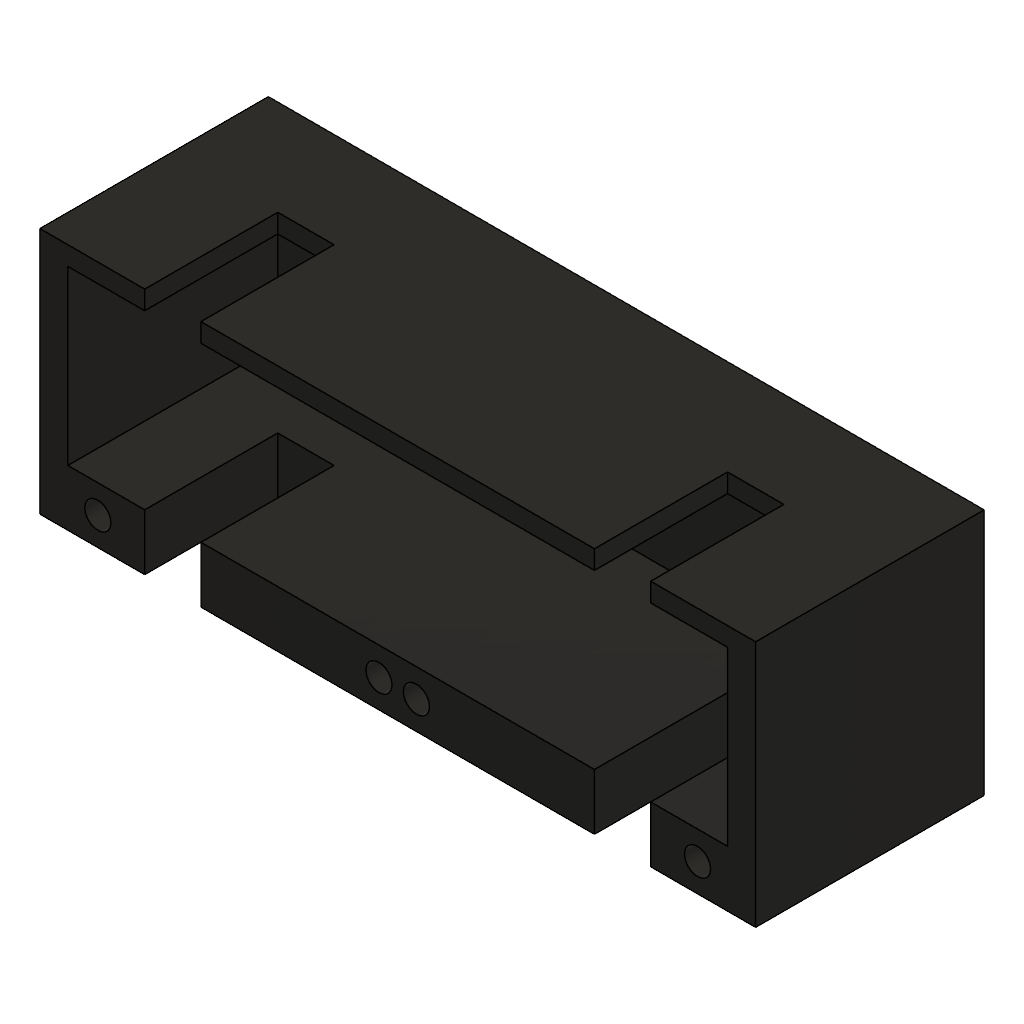
Robot_Assembly (Autodesk Fusion 360 archive; units mm, degrees)
design "Motor cradles"
part number: 2026-11-12-22-37-27-896
Autodesk Fusion 360 part; units mm, degrees
sketch "Sketch3" plane through (0, 0, 0) normal (0, 0, 1) x (1, 0, 0)
  line L0 (38.2, -13.2) -> (-38.2, -13.2)
  line L1 (-38.2, -13.2) -> (-38.2, 13.2)
  line L2 (-38.2, 13.2) -> (38.2, 13.2)
  line L3 (38.2, 13.2) -> (38.2, -13.2)
  line L4 (38.2, -13.2) -> (-38.2, 13.2) construction
  line L5 (-38.2, -13.2) -> (38.2, 13.2) construction
  dimension "d11" = 76.4
  dimension "d12" = 26.4
  constraint horizontal L0
  constraint perpendicular L0 L1
  constraint parallel L0 L2
  constraint parallel L1 L3
  constraint coincident L4 origin
  constraint coincident L5 origin
  measures "d11" distance of L0.start L0.end
  measures "d12" distance of L0.start L2.end
extrude "Extrude2" add sketch "Sketch3" along normal blind 24.4
sketch "Sketch5" plane through (0, 0, 24.4) normal (0, 0, 1) x (1, 0, 0)
  line L0 (38.2, 13.2) -> (-38.2, 13.2)
  line L1 (-38.2, 13.2) -> (-38.2, -13.2)
  line L2 (-38.2, -13.2) -> (38.2, -13.2)
  line L3 (38.2, -13.2) -> (38.2, 13.2)
  line L4 (35.2, -7.2) -> (-35.2, -7.2)
  line L5 (-35.2, -7.2) -> (-35.2, 11.2)
  line L6 (-35.2, 11.2) -> (35.2, 11.2)
  line L7 (35.2, 11.2) -> (35.2, -7.2)
  line L8 (35.2, -7.2) -> (-35.2, 11.2) construction
  line L9 (-35.2, -7.2) -> (35.2, 11.2) construction
  circle A0 centre (-32, -10.2) radius 1.4
  circle A1 centre (-2, -10.2) radius 1.4
  circle A2 centre (2, -10.2) radius 1.4
  circle A3 centre (32, -10.2) radius 1.4
  point P0 (0, 2)
  dimension "d15" = 6
  dimension "d16" = 3
  dimension "d17" = 70.4
  dimension "d18" = 18.4
  dimension "d19" = 2.8
  dimension "d20" = 3
  dimension "d21" = 6.2
  dimension "d22" = 2.8
  dimension "d23" = 3
  dimension "d24" = 36.2
  dimension "d25" = 2.8
  dimension "d26" = 3
  dimension "d27" = 40.2
  dimension "d28" = 2.8
  dimension "d29" = 3
  dimension "d30" = 70.2
  constraint horizontal L4
  constraint perpendicular L4 L5
  constraint parallel L4 L6
  constraint parallel L5 L7
  constraint coincident L8 P0
  constraint coincident L9 P0
  measures "d15" distance of L2 L4
  measures "d16" distance of L1 L5
  measures "d17" distance of L4.start L4.end
  measures "d18" distance of L4.start L6.end
  measures "d19" diameter of A0
  measures "d20" distance of L2 A0.centre
  measures "d21" distance of L1 A0.centre
  measures "d22" diameter of A1
  measures "d23" distance of L2 A1.centre
  measures "d24" distance of L1 A1.centre
  measures "d25" diameter of A2
  measures "d26" distance of L2 A2.centre
  measures "d27" distance of L1 A2.centre
  measures "d28" diameter of A3
  measures "d29" distance of L2 A3.centre
  measures "d30" distance of L1 A3.centre
extrude "Extrude3" cut sketch "Sketch5" against normal blind 22.4 contours L4 L5 L6 L7
extrude "Extrude4" cut sketch "Sketch5" against normal blind 10 contours A0 | A1 | A2 | A3
sketch "Sketch6" plane through (0, 0, 24.4) normal (0, 0, 1) x (1, 0, 0)
  line L0 (38.2, 13.2) -> (-38.2, 13.2)
  line L1 (-38.2, 13.2) -> (-38.2, -13.2)
  line L2 (-38.2, -13.2) -> (38.2, -13.2)
  line L3 (38.2, -13.2) -> (38.2, 13.2)
  line L4 (-35.2, -7.2) -> (-35.2, 11.2)
  line L5 (-35.2, 11.2) -> (35.2, 11.2)
  line L6 (35.2, 11.2) -> (35.2, -7.2)
  line L7 (35.2, -7.2) -> (-35.2, -7.2)
  circle A0 centre (32, -10.2) radius 1.4
  circle A1 centre (-32, -10.2) radius 1.4
  circle A2 centre (2, -10.2) radius 1.4
  circle A3 centre (-2, -10.2) radius 1.4
  line L8 (-27, 17.0474) -> (-21, 17.0474)
  line L9 (-21, 17.0474) -> (-21, -21.5101)
  line L10 (-21, -21.5101) -> (-27, -21.5101)
  line L11 (-27, -21.5101) -> (-27, 17.0474)
  line L12 (21, 17.0474) -> (27, 17.0474)
  line L13 (27, 17.0474) -> (27, -21.5101)
  line L14 (27, -21.5101) -> (21, -21.5101)
  line L15 (21, -21.5101) -> (21, 17.0474)
  dimension "d35" = 6
  dimension "d36" = 11.2
  dimension "d37" = 6
  dimension "d38" = 59.2
  constraint horizontal L8
  constraint vertical L9
  constraint horizontal L10
  constraint vertical L11
  constraint horizontal L12
  constraint vertical L13
  constraint horizontal L14
  constraint vertical L15
  measures "d35" distance of L8.start L8.end
  measures "d36" distance of L1 L11
  measures "d37" distance of L12.start L12.end
  measures "d38" distance of L1 L15
extrude "Extrude5" cut sketch "Sketch6" against normal blind 14.2 contours L0 L5 L13 L15 | L0 L12 L13 L15 | L5 L7 L13 L15 | L2 L13 L14 L15 | L2 L7 L13 L15 | L0 L5 L9 L11 | L0 L8 L9 L11 | L5 L7 L9 L11 | L2 L9 L10 L11 | L2 L7 L9 L11

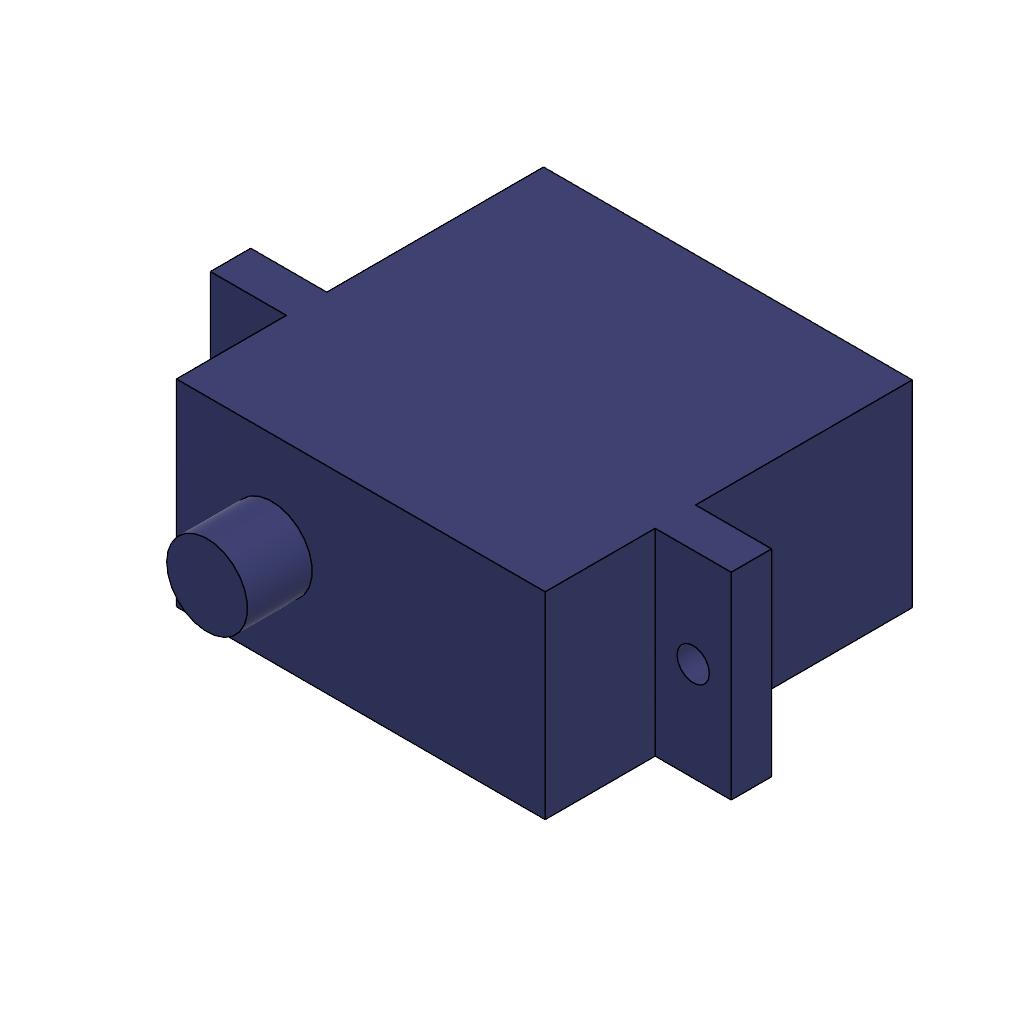
design "Servo_SG90"
part number: 2026-11-06-21-26-01-981
Autodesk Fusion 360 part; units mm, degrees
sketch "Sketch1" plane through (0, 0, 0) normal (0, 0, 1) x (1, 0, 0)
  line L0 (11.4, -6.1) -> (-11.4, -6.1)
  line L1 (-11.4, -6.1) -> (-11.4, 6.1)
  line L2 (-11.4, 6.1) -> (11.4, 6.1)
  line L3 (11.4, 6.1) -> (11.4, -6.1)
  line L4 (11.4, -6.1) -> (-11.4, 6.1) construction
  line L5 (-11.4, -6.1) -> (11.4, 6.1) construction
  dimension "d1" = 22.8
  dimension "d2" = 12.2
  constraint horizontal L0
  constraint perpendicular L0 L1
  constraint parallel L0 L2
  constraint parallel L1 L3
  constraint coincident L4 origin
  constraint coincident L5 origin
  measures "d1" distance of L1.end L2.end
  measures "d2" distance of L0.start L2.end
sketch "Sketch2" plane through (0, 0, 0) normal (0, 0, 1) x (1, 0, 0)
  line L0 (11.4, -6.1) -> (-11.4, -6.1)
  line L1 (-11.4, -6.1) -> (-11.4, 6.1)
  line L2 (-11.4, 6.1) -> (11.4, 6.1)
  line L3 (11.4, 6.1) -> (11.4, -6.1)
  line L4 (11.4, -6.1) -> (-11.4, 6.1) construction
  line L5 (-11.4, -6.1) -> (11.4, 6.1) construction
  dimension "d5" = 22.8
  dimension "d6" = 12.2
  constraint horizontal L0
  constraint perpendicular L0 L1
  constraint parallel L0 L2
  constraint parallel L1 L3
  constraint coincident L4 origin
  constraint coincident L5 origin
  measures "d5" distance of L0.start L0.end
  measures "d6" distance of L0.start L2.end
extrude "Extrude2" add sketch "Sketch2" along normal blind 22.7
sketch "Sketch3" plane through (0, 0, 22.7) normal (0, 0, 1) x (1, 0, 0)
  line L0 (11.4, 6.1) -> (-11.4, 6.1)
  line L1 (-11.4, 6.1) -> (-11.4, -6.1)
  line L2 (-11.4, -6.1) -> (11.4, -6.1)
  line L3 (11.4, -6.1) -> (11.4, 6.1)
  line L4 (16.1, -6.1) -> (-16.1, -6.1)
  line L5 (-16.1, -6.1) -> (-16.1, 6.1)
  line L6 (-16.1, 6.1) -> (16.1, 6.1)
  line L7 (16.1, 6.1) -> (16.1, -6.1)
  line L8 (16.1, -6.1) -> (-16.1, 6.1) construction
  line L9 (-16.1, -6.1) -> (16.1, 6.1) construction
  dimension "d9" = 12.2
  dimension "d10" = 32.2
  constraint horizontal L4
  constraint perpendicular L4 L5
  constraint parallel L4 L6
  constraint parallel L5 L7
  constraint coincident L8 origin
  constraint coincident L9 origin
  measures "d9" distance of L4.end L5.end
  measures "d10" distance of L5.end L6.end
sketch "Sketch4" plane through (0, 0, 38.6) normal (0, 0, 1) x (1, 0, 0)
ref_plane "WorkPlane1" through (0, 0, 13.4) normal (0, 0, 1) x (1, 0, 0)
sketch "Sketch6" plane through (0, 0, 13.4) normal (0, 0, 1) x (1, 0, 0)
  line L0 (16.1, -6.1) -> (-16.1, -6.1)
  line L1 (-16.1, -6.1) -> (-16.1, 6.1)
  line L2 (-16.1, 6.1) -> (16.1, 6.1)
  line L3 (16.1, 6.1) -> (16.1, -6.1)
  line L4 (16.1, -6.1) -> (-16.1, 6.1) construction
  line L5 (-16.1, -6.1) -> (16.1, 6.1) construction
  dimension "d18" = 32.2
  dimension "d19" = 12.2
  constraint horizontal L0
  constraint perpendicular L0 L1
  constraint parallel L0 L2
  constraint parallel L1 L3
  constraint coincident L4 origin
  constraint coincident L5 origin
  measures "d18" distance of L1.end L2.end
  measures "d19" distance of L0.start L2.end
extrude "Extrude4" add sketch "Sketch6" along normal blind 2.5
sketch "Sketch7" plane through (0, 0, 15.9) normal (0, 0, 1) x (1, 0, 0)
  line L0 (-11.4, -6.1) -> (-11.4, 6.1)
  line L1 (-11.4, 6.1) -> (-16.1, 6.1)
  line L2 (-16.1, 6.1) -> (-16.1, -6.1)
  line L3 (-16.1, -6.1) -> (-11.4, -6.1)
  circle A0 centre (-13.75, 0) radius 1
  dimension "d22" = 2
  dimension "d23" = 2.35
  dimension "d24" = 6.1
  measures "d22" diameter of A0
  measures "d23" distance of L2 A0.centre
  measures "d24" distance of L1 A0.centre
sketch "Sketch8" plane through (0, 0, 15.9) normal (0, 0, 1) x (1, 0, 0)
  line L0 (11.4, 6.1) -> (11.4, -6.1)
  line L1 (11.4, -6.1) -> (16.1, -6.1)
  line L2 (16.1, -6.1) -> (16.1, 6.1)
  line L3 (16.1, 6.1) -> (11.4, 6.1)
  circle A0 centre (13.75, 0) radius 1
  dimension "d25" = 2
  dimension "d26" = 2.35
  dimension "d27" = 6.1
  measures "d25" diameter of A0
  measures "d26" distance of L0 A0.centre
  measures "d27" distance of L3 A0.centre
extrude "Extrude5" cut sketch "Sketch7" sketch "Sketch8" against normal blind 10 contours A0 of sketch 2 contours A0
sketch "Sketch9" plane through (0, 0, 22.7) normal (0, 0, 1) x (1, 0, 0)
  line L0 (11.4, 6.1) -> (-11.4, 6.1)
  line L1 (-11.4, 6.1) -> (-11.4, -6.1)
  line L2 (-11.4, -6.1) -> (11.4, -6.1)
  line L3 (11.4, -6.1) -> (11.4, 6.1)
  circle A0 centre (-5.5, 0) radius 2.5
  dimension "d30" = 5
  dimension "d31" = 5.9
  dimension "d32" = 6.1
  measures "d30" diameter of A0
  measures "d31" distance of L1 A0.centre
  measures "d32" distance of L0 A0.centre
extrude "Extrude6" add sketch "Sketch9" along normal blind 4 contours A0

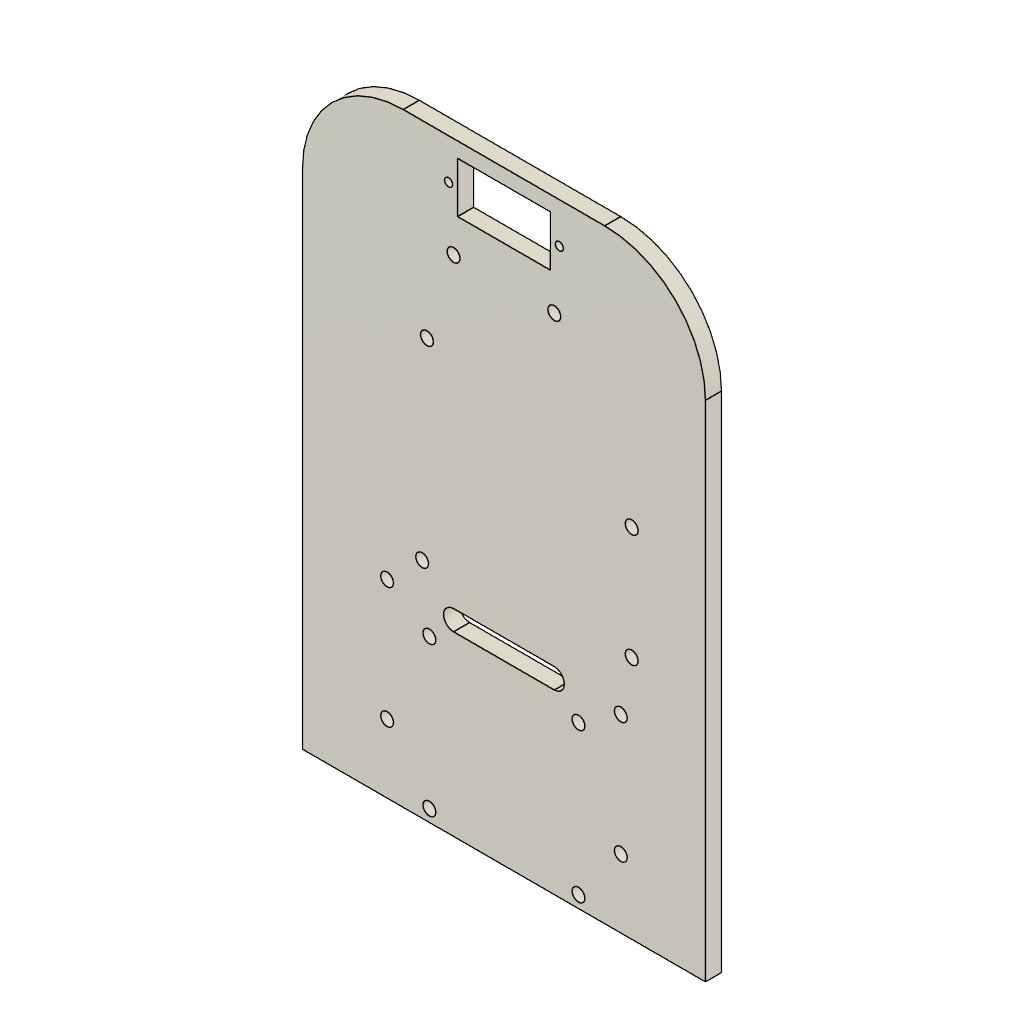
design "Chassis plate"
part number: 2026-11-10-16-59-27-639
Autodesk Fusion 360 part; units mm, degrees
sketch "Sketch1" plane through (0, 0, 0) normal (0, 0, 1) x (1, 0, 0)
  line L0 (50, -75) -> (-50, -75)
  line L1 (-50, -75) -> (-50, 50)
  line L2 (-25, 75) -> (25, 75)
  line L3 (50, 50) -> (50, -75)
  line L4 (50, -75) -> (-50, 75) construction
  line L5 (-50, -75) -> (50, 75) construction
  arc A0 (-25, 75) -> (-50, 50) centre (-25, 50) ccw
  arc A1 (50, 50) -> (25, 75) centre (25, 50) ccw
  circle A2 centre (-18.5, -72) radius 1.6
  circle A3 centre (18.5, -72) radius 1.6
  circle A4 centre (-18.5, -35) radius 1.6
  circle A5 centre (18.5, -35) radius 1.6
  circle A6 centre (-20.3, -19.5) radius 1.6
  circle A7 centre (-19.1, 28.8) radius 1.6
  circle A8 centre (31.7, -14.4) radius 1.6
  circle A9 centre (31.7, 13.6) radius 1.6
  circle A10 centre (-29, -58) radius 1.6
  circle A11 centre (-29, -28) radius 1.6
  circle A12 centre (29, -58) radius 1.6
  circle A13 centre (29, -28) radius 1.6
  circle A14 centre (-12.5, 50) radius 1.6
  circle A15 centre (12.5, 50) radius 1.6
  circle A16 centre (-13.75, 65) radius 1
  circle A17 centre (13.75, 65) radius 1
  line L6 (11.5, 58.75) -> (-11.5, 58.75)
  line L7 (-11.5, 58.75) -> (-11.5, 71.25)
  line L8 (-11.5, 71.25) -> (11.5, 71.25)
  line L9 (11.5, 71.25) -> (11.5, 58.75)
  line L10 (11.5, 58.75) -> (-11.5, 71.25) construction
  line L11 (-11.5, 58.75) -> (11.5, 71.25) construction
  line L12 (-12.5, -31) -> (12.5, -31)
  arc A18 (12.5, -31) -> (12.5, -26) centre (12.5, -28.5) ccw
  line L13 (12.5, -26) -> (-12.5, -26)
  arc A19 (-12.5, -26) -> (-12.5, -31) centre (-12.5, -28.5) ccw
  point P0 (0, 65)
  dimension "d1" = 100
  dimension "d2" = 150
  dimension "d3" = 25
  dimension "d4" = 25
  dimension "d5" = 3.2
  dimension "d6" = 31.5
  dimension "d7" = 3
  dimension "d8" = 3.2
  dimension "d9" = 3
  dimension "d10" = 68.5
  dimension "d11" = 3.2
  dimension "d12" = 31.5
  dimension "d13" = 40
  dimension "d14" = 3.2
  dimension "d15" = 68.5
  dimension "d16" = 40
  dimension "d17" = 3.2
  dimension "d18" = 29.7
  dimension "d19" = 55.5
  dimension "d20" = 3.2
  dimension "d21" = 30.9
  dimension "d22" = 103.8
  dimension "d23" = 3.2
  dimension "d24" = 81.7
  dimension "d25" = 60.6
  dimension "d26" = 3.2
  dimension "d27" = 81.7
  dimension "d28" = 88.6
  dimension "d29" = 3.2
  dimension "d30" = 21
  dimension "d31" = 17
  dimension "d32" = 3.2
  dimension "d33" = 21
  dimension "d34" = 47
  dimension "d35" = 3.2
  dimension "d36" = 79
  dimension "d37" = 17
  dimension "d38" = 3.2
  dimension "d39" = 79
  dimension "d40" = 47
  dimension "d41" = 3.2
  dimension "d42" = 37.5
  dimension "d43" = 125
  dimension "d44" = 3.2
  dimension "d45" = 62.5
  dimension "d46" = 125
  dimension "d47" = 2
  dimension "d48" = 36.25
  dimension "d49" = 140
  dimension "d50" = 2
  dimension "d51" = 63.75
  dimension "d52" = 140
  dimension "d53" = 12.5
  dimension "d54" = 23
  dimension "d55" = 50
  dimension "d56" = 140
  dimension "d57" = 5
  dimension "d58" = 37.5
  dimension "d59" = 46.5
  constraint horizontal L0
  constraint perpendicular L0 L1
  constraint parallel L0 L2
  constraint parallel L1 L3
  constraint coincident L4 origin
  constraint coincident L5 origin
  constraint coincident L4.end L2
  constraint coincident L4.end L1
  constraint tangent L2 A0
  constraint tangent L1 A0
  constraint coincident L5.end L2
  constraint coincident L5.end L3
  constraint tangent L2 A1
  constraint tangent L3 A1
  constraint horizontal L6
  constraint perpendicular L6 L7
  constraint parallel L6 L8
  constraint parallel L7 L9
  constraint coincident L10 P0
  constraint coincident L11 P0
  constraint tangent L12 A18
  constraint tangent A18 L13
  constraint parallel L12 L13
  constraint tangent L13 A19
  constraint tangent L12 A19
  measures "d1" distance of L0.start L0.end
  measures "d2" distance of L0.start L5.end
  measures "d3" radius of A0
  measures "d4" radius of A1
  measures "d5" diameter of A2
  measures "d6" distance of L1 A2.centre
  measures "d7" distance of L0 A2.centre
  measures "d8" diameter of A3
  measures "d9" distance of L0 A3.centre
  measures "d10" distance of L1 A3.centre
  measures "d11" diameter of A4
  measures "d12" distance of L1 A4.centre
  measures "d13" distance of L0 A4.centre
  measures "d14" diameter of A5
  measures "d15" distance of L1 A5.centre
  measures "d16" distance of L0 A5.centre
  measures "d17" diameter of A6
  measures "d18" distance of L1 A6.centre
  measures "d19" distance of L0 A6.centre
  measures "d20" diameter of A7
  measures "d21" distance of L1 A7.centre
  measures "d22" distance of L0 A7.centre
  measures "d23" diameter of A8
  measures "d24" distance of L1 A8.centre
  measures "d25" distance of L0 A8.centre
  measures "d26" diameter of A9
  measures "d27" distance of L1 A9.centre
  measures "d28" distance of L0 A9.centre
  measures "d29" diameter of A10
  measures "d30" distance of L1 A10.centre
  measures "d31" distance of L0 A10.centre
  measures "d32" diameter of A11
  measures "d33" distance of L1 A11.centre
  measures "d34" distance of L0 A11.centre
  measures "d35" diameter of A12
  measures "d36" distance of L1 A12.centre
  measures "d37" distance of L0 A12.centre
  measures "d38" diameter of A13
  measures "d39" distance of L1 A13.centre
  measures "d40" distance of L0 A13.centre
  measures "d41" diameter of A14
  measures "d42" distance of L1 A14.centre
  measures "d43" distance of L0 A14.centre
  measures "d44" diameter of A15
  measures "d45" distance of L1 A15.centre
  measures "d46" distance of L0 A15.centre
  measures "d47" diameter of A16
  measures "d48" distance of L1 A16.centre
  measures "d49" distance of L0 A16.centre
  measures "d50" diameter of A17
  measures "d51" distance of L1 A17.centre
  measures "d52" distance of L0 A17.centre
  measures "d53" distance of L6.start L8.end
  measures "d54" distance of L7.end L8.end
  measures "d55" distance of L1 P0
  measures "d56" distance of L0 P0
  measures "d57" diameter of A18
  measures "d58" distance of L1 A19.centre
  measures "d59" distance of L0 A19.centre
extrude "Extrude1" add sketch "Sketch1" along normal blind 4

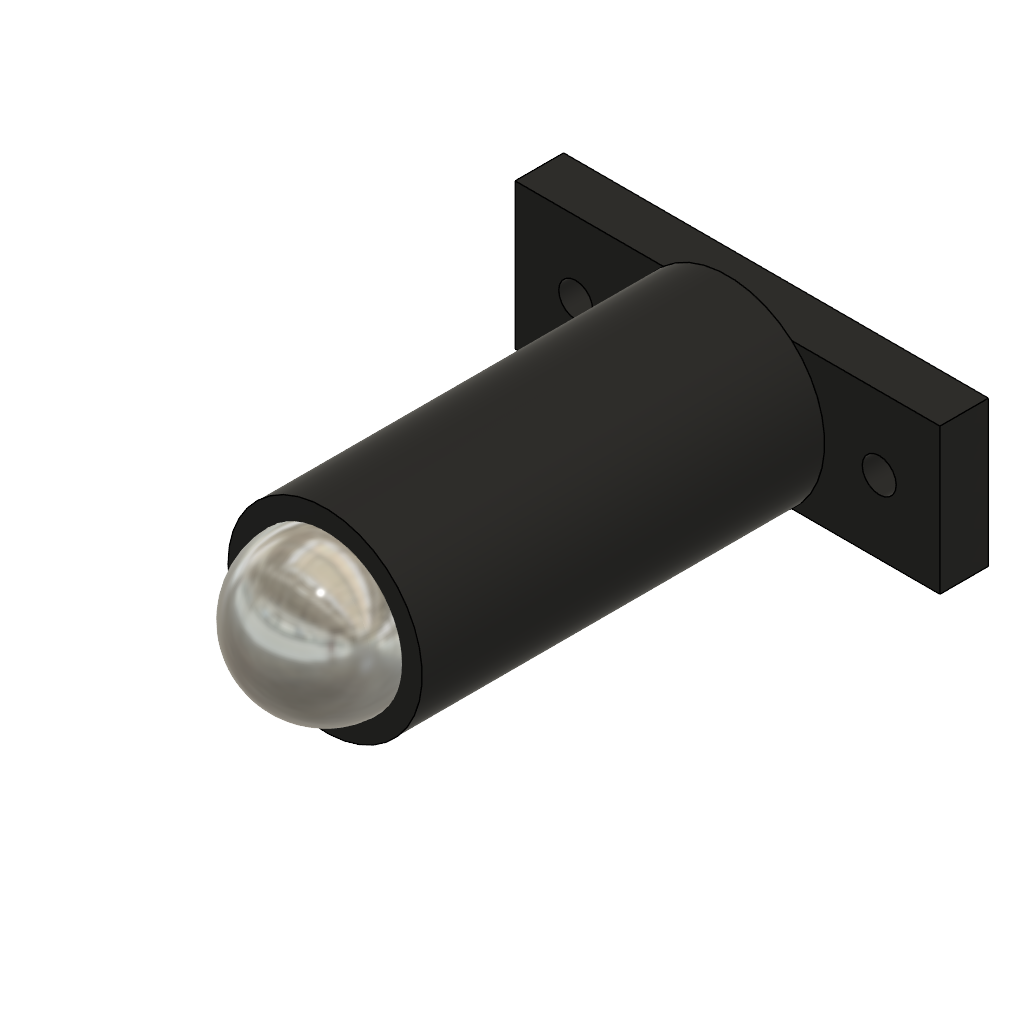
design "Caster"
part number: 2026-11-12-23-13-29-556
Autodesk Fusion 360 part; units mm, degrees
sketch "Sketch1" plane through (0, 0, 0) normal (0, 0, 1) x (1, 0, 0)
  line L0 (17.5, -6) -> (-17.5, -6)
  line L1 (-17.5, -6) -> (-17.5, 6)
  line L2 (-17.5, 6) -> (17.5, 6)
  line L3 (17.5, 6) -> (17.5, -6)
  line L4 (17.5, -6) -> (-17.5, 6) construction
  line L5 (-17.5, -6) -> (17.5, 6) construction
  circle A0 centre (-12.5, 0) radius 1.4
  circle A1 centre (12.5, 0) radius 1.4
  dimension "d1" = 35
  dimension "d2" = 12
  dimension "d3" = 2.8
  dimension "d4" = 12.5
  dimension "d5" = 2.8
  dimension "d6" = 12.5
  dimension "d7" = 6
  dimension "d8" = 6
  constraint horizontal L0
  constraint perpendicular L0 L1
  constraint parallel L0 L2
  constraint parallel L1 L3
  constraint coincident L4 origin
  constraint coincident L5 origin
  measures "d1" distance of L0.start L0.end
  measures "d2" distance of L0.start L2.end
  measures "d3" diameter of A0
  measures "d4" horizontal distance of origin A0.centre
  measures "d5" diameter of A1
  measures "d6" horizontal distance of origin A1.centre
  measures "d7" distance of L2 A0.centre
  measures "d8" distance of L2 A1.centre
extrude "Extrude1" add sketch "Sketch1" along normal blind 4 makes body 1
sketch "Sketch2" plane through (0, 0, 4) normal (0, 0, 1) x (1, 0, 0)
  circle A0 centre (12.5, 0) radius 1.4
  circle A1 centre (-12.5, 0) radius 1.4
  line L0 (17.5, 6) -> (-17.5, 6)
  line L1 (-17.5, 6) -> (-17.5, -6)
  line L2 (-17.5, -6) -> (17.5, -6)
  line L3 (17.5, -6) -> (17.5, 6)
  circle A2 centre (0, 0) radius 8
  dimension "d11" = 16
  constraint coincident A2.centre origin
  measures "d11" diameter of A2
extrude "Extrude2" add sketch "Sketch2" along normal blind 33.15 contours L0 L2 A2 | L0 A2 | L2 A2 bodies 1
sphere "SpherePrimitive1" add diameter 12.7 placed x (1, 0, 0) y (0, 1, 0) z (0, 0, 1) at (0, 0, 37.15) separate body makes body 2

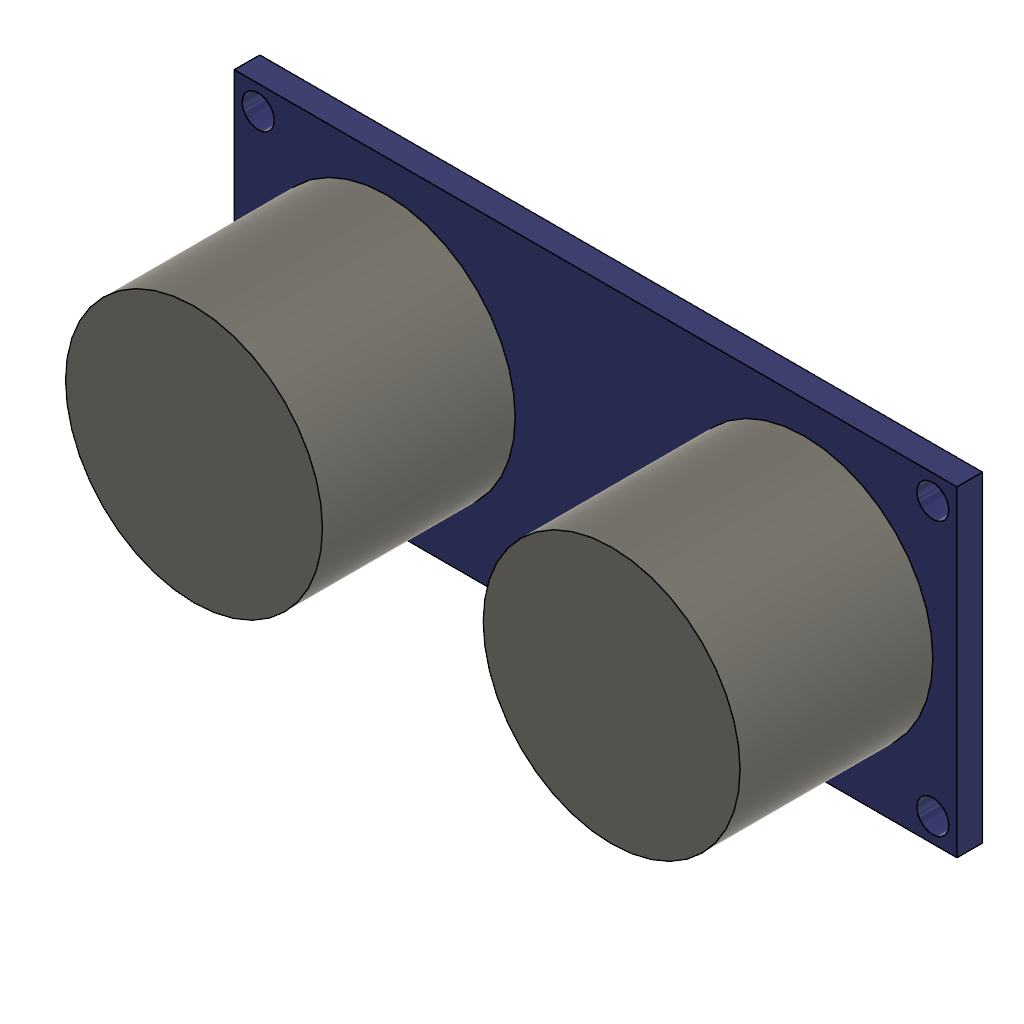
design "HC_SR04"
part number: 2026-11-10-16-47-09-081
Autodesk Fusion 360 part; units mm, degrees
sketch "Sketch1" plane through (0, 0, 0) normal (0, 0, 1) x (1, 0, 0)
  line L0 (22.5, -10) -> (-22.5, -10)
  line L1 (-22.5, -10) -> (-22.5, 10)
  line L2 (-22.5, 10) -> (22.5, 10)
  line L3 (22.5, 10) -> (22.5, -10)
  line L4 (22.5, -10) -> (-22.5, 10) construction
  line L5 (-22.5, -10) -> (22.5, 10) construction
  circle A0 centre (-21, 8.5) radius 1
  circle A1 centre (21, 8.5) radius 1
  circle A2 centre (21, -8.5) radius 1
  circle A3 centre (-21, -8.5) radius 1
  point P0 (21, 8.5)
  point P1 (21, -8.5)
  point P2 (-21, -8.5)
  dimension "d1" = 45
  dimension "d2" = 20
  dimension "d3" = 2
  dimension "d4" = 1.5
  dimension "d5" = 1.5
  dimension "d6" = 2
  dimension "d7" = 2
  dimension "d8" = 2
  constraint horizontal L0
  constraint perpendicular L0 L1
  constraint parallel L0 L2
  constraint parallel L1 L3
  constraint coincident L4 origin
  constraint coincident L5 origin
  constraint coincident P0 A1.centre
  constraint coincident P1 A2.centre
  constraint coincident P2 A3.centre
  measures "d1" distance of L0.start L0.end
  measures "d2" distance of L0.start L2.end
  measures "d3" diameter of A0
  measures "d4" distance of L1 A0.centre
  measures "d5" distance of L2 A0.centre
  measures "d6" diameter of A1
  measures "d7" diameter of A2
  measures "d8" diameter of A3
extrude "Extrude1" add sketch "Sketch1" along normal blind 1.6
sketch "Sketch2" plane through (0, 0, 1.6) normal (0, 0, 1) x (1, 0, 0)
  circle A0 centre (-21, -8.5) radius 1
  circle A1 centre (21, -8.5) radius 1
  circle A2 centre (21, 8.5) radius 1
  circle A3 centre (-21, 8.5) radius 1
  line L0 (22.5, 10) -> (-22.5, 10)
  line L1 (-22.5, 10) -> (-22.5, -10)
  line L2 (-22.5, -10) -> (22.5, -10)
  line L3 (22.5, -10) -> (22.5, 10)
  circle A4 centre (-13, 0) radius 8
  circle A5 centre (13, 0) radius 8
  point P0 (13, 0)
  dimension "d11" = 16
  dimension "d12" = 9.5
  dimension "d13" = 10
  dimension "d14" = 16
  constraint coincident P0 A5.centre
  measures "d11" diameter of A4
  measures "d12" distance of L1 A4.centre
  measures "d13" distance of L2 A4.centre
  measures "d14" diameter of A5
extrude "Extrude2" add sketch "Sketch2" along normal blind 12 contours A4 | A5

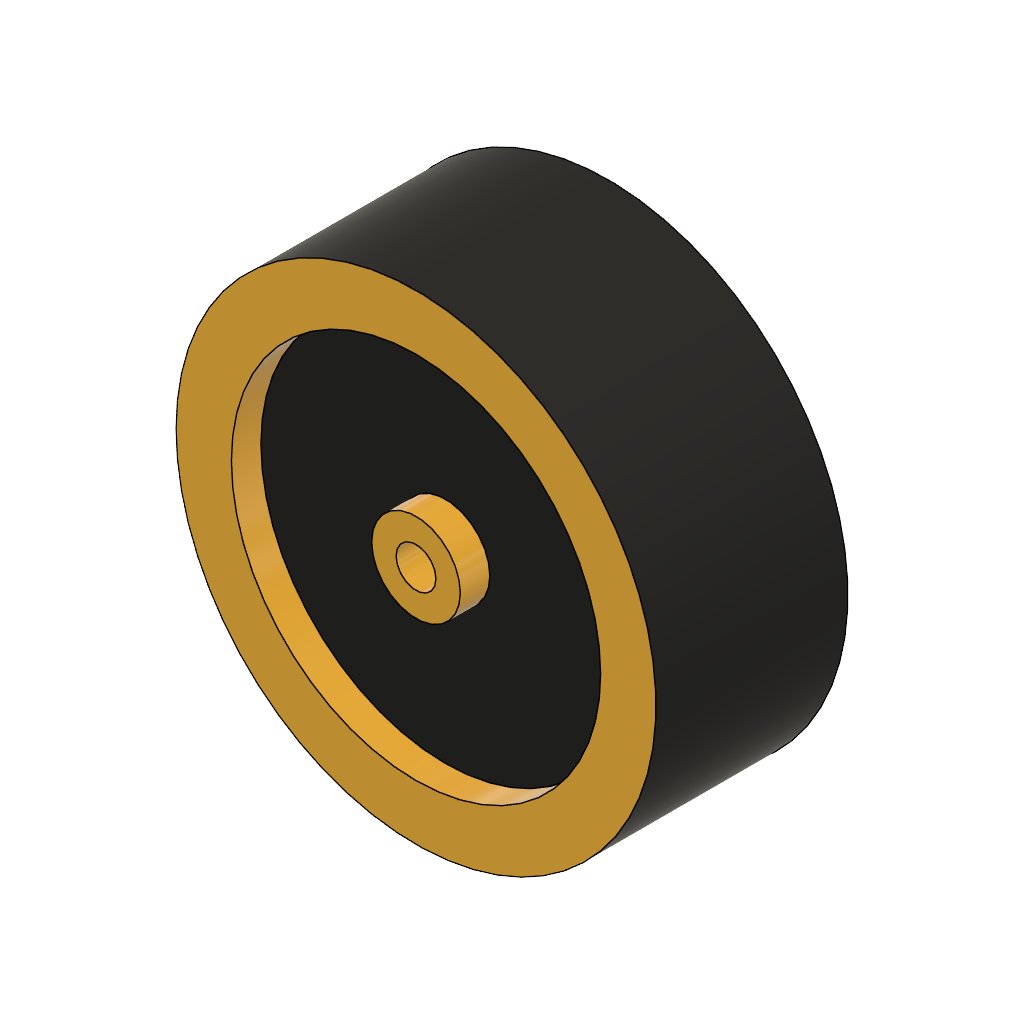
design "Wheel_65"
part number: 2026-11-09-17-20-55-828
Autodesk Fusion 360 part; units mm, degrees
sketch "Sketch1" plane through (0, 0, 0) normal (0, 0, 1) x (1, 0, 0)
  circle A0 centre (0, 0) radius 32.5
  circle A1 centre (0, 0) radius 2.7
  dimension "d1" = 65
  dimension "d2" = 5.4
  constraint coincident A0.centre A1.centre
  constraint concentric A0 A1
  measures "d1" diameter of A0
  measures "d2" diameter of A1
extrude "Extrude1" add sketch "Sketch1" along normal mid plane 26
sketch "Sketch2" plane through (0, 0, 13) normal (0, 0, 1) x (1, 0, 0)
  circle A0 centre (0, 0) radius 2.7
  circle A1 centre (0, 0) radius 32.5
  circle A2 centre (0, 0) radius 25
  circle A3 centre (0, 0) radius 6
  dimension "d5" = 50
  dimension "d6" = 12
  constraint coincident A0.centre A1.centre
  constraint concentric A2 A3
  measures "d5" diameter of A2
  measures "d6" diameter of A3
extrude "Extrude2" cut sketch "Sketch2" against normal blind 4 contours A2
sketch "Sketch3" plane through (0, 0, -13) normal (0, 0, -1) x (-1, 0, 0)
  circle A0 centre (0, 0) radius 2.7
  circle A1 centre (0, 0) radius 32.5
  circle A2 centre (0, 0) radius 25
  circle A3 centre (0, 0) radius 6
  dimension "d9" = 50
  dimension "d10" = 12
  constraint coincident A0.centre A1.centre
  constraint concentric A2 A3
  measures "d9" diameter of A2
  measures "d10" diameter of A3
extrude "Extrude3" cut sketch "Sketch3" against normal blind 4 contours A2

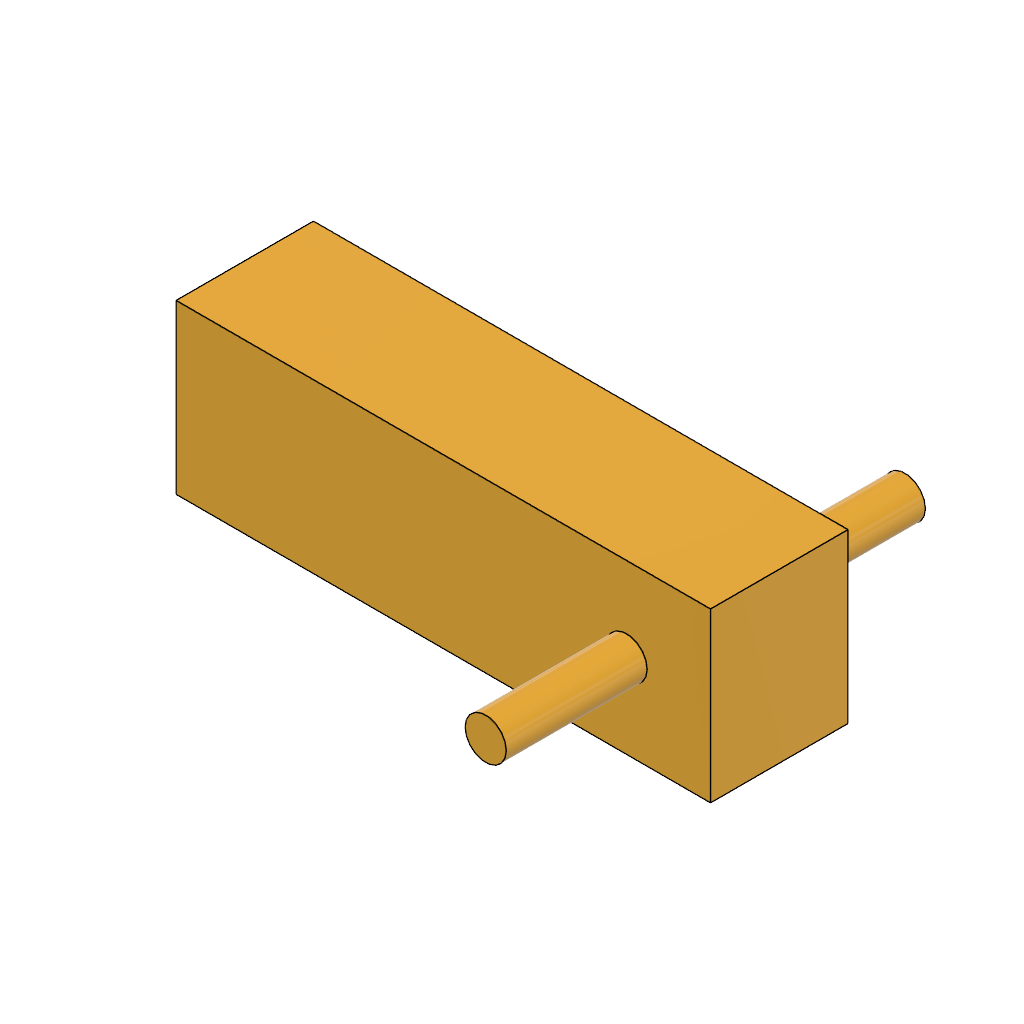
design "TT_Motor"
part number: 2026-11-09-17-13-42-510
Autodesk Fusion 360 part; units mm, degrees
sketch "Sketch1" plane through (0, 0, 0) normal (0, 0, 1) x (1, 0, 0)
  line L0 (35, -11) -> (-35, -11)
  line L1 (-35, -11) -> (-35, 11)
  line L2 (-35, 11) -> (35, 11)
  line L3 (35, 11) -> (35, -11)
  line L4 (35, -11) -> (-35, 11) construction
  line L5 (-35, -11) -> (35, 11) construction
  circle A0 centre (24, 0) radius 2.7
  dimension "d1" = 22
  dimension "d2" = 70
  dimension "d3" = 5.4
  dimension "d4" = 11
  dimension "d5" = 11
  constraint horizontal L0
  constraint perpendicular L0 L1
  constraint parallel L0 L2
  constraint parallel L1 L3
  constraint coincident L4 origin
  constraint coincident L5 origin
  measures "d1" distance of L0.end L1.end
  measures "d2" distance of L1.end L2.end
  measures "d3" diameter of A0
  measures "d4" distance of L0 A0.centre
  measures "d5" distance of L3 A0.centre
extrude "Extrude1" add sketch "Sketch1" along normal mid plane 18
sketch "Sketch2" plane through (0, 0, 9) normal (0, 0, 1) x (1, 0, 0)
  circle A0 centre (24, 0) radius 2.7
  line L0 (35, 11) -> (-35, 11)
  line L1 (-35, 11) -> (-35, -11)
  line L2 (-35, -11) -> (35, -11)
  line L3 (35, -11) -> (35, 11)
  circle A1 centre (24, 0) radius 2.7
  constraint concentric A0 A1
extrude "Extrude2" add sketch "Sketch2" along normal mid plane 36.9 contours A0 A1
sketch "Sketch3" plane through (0, 0, -9) normal (0, 0, -1) x (-1, 0, 0)
  line L0 (35, 11) -> (-35, 11)
  line L1 (-35, 11) -> (-35, -11)
  line L2 (-35, -11) -> (35, -11)
  line L3 (35, -11) -> (35, 11)
  circle A0 centre (-24, 0) radius 2.7
  circle A1 centre (-24, 0) radius 2.7
extrude "Extrude3" add sketch "Sketch3" along normal mid plane 36.9 contours A0 A1

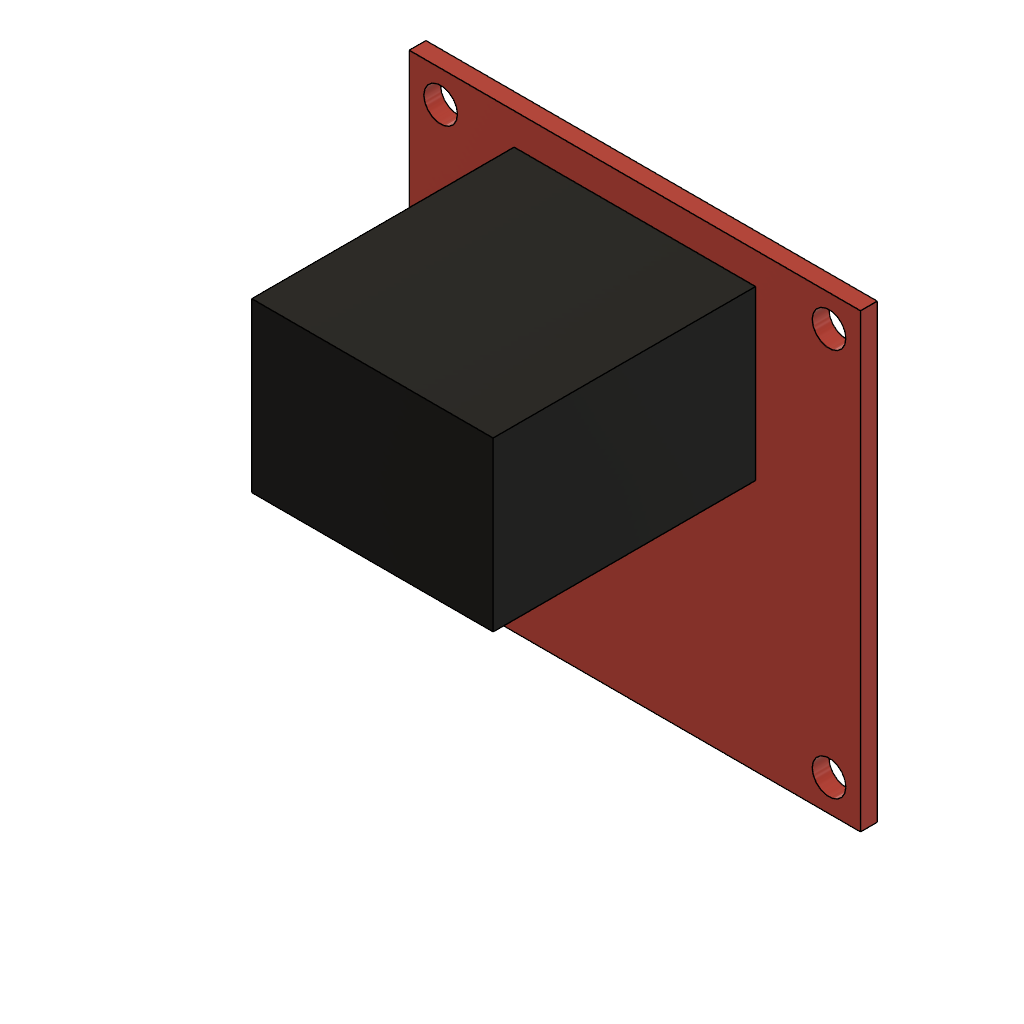
design "L298N"
part number: 2026-11-10-16-33-09-459
Autodesk Fusion 360 part; units mm, degrees
sketch "Sketch1" plane through (0, 0, 0) normal (0, 0, 1) x (1, 0, 0)
  line L0 (21.5, -21.5) -> (-21.5, -21.5)
  line L1 (-21.5, -21.5) -> (-21.5, 21.5)
  line L2 (-21.5, 21.5) -> (21.5, 21.5)
  line L3 (21.5, 21.5) -> (21.5, -21.5)
  line L4 (21.5, -21.5) -> (-21.5, 21.5) construction
  line L5 (-21.5, -21.5) -> (21.5, 21.5) construction
  circle A0 centre (-18.5, 18.5) radius 1.6
  circle A1 centre (18.5, 18.5) radius 1.6
  circle A2 centre (-18.5, -18.5) radius 1.6
  circle A3 centre (18.5, -18.5) radius 1.6
  dimension "d1" = 43
  dimension "d2" = 3.2
  dimension "d3" = 3
  dimension "d4" = 3
  dimension "d5" = 3.2
  dimension "d6" = 40
  dimension "d7" = 3
  dimension "d8" = 3.2
  dimension "d9" = 40
  dimension "d10" = 3
  dimension "d11" = 3.2
  dimension "d12" = 40
  dimension "d13" = 40
  constraint horizontal L0
  constraint perpendicular L0 L1
  constraint parallel L0 L2
  constraint parallel L1 L3
  constraint coincident L4 origin
  constraint coincident L5 origin
  constraint equal L1 L2
  constraint coincident L4 A0.centre
  constraint coincident L5 A2.centre
  measures "d1" distance of L0.end L1.end
  measures "d2" diameter of A0
  measures "d3" distance of L2 A0.centre
  measures "d4" distance of L1 A0.centre
  measures "d5" diameter of A1
  measures "d6" distance of L1 A1.centre
  measures "d7" distance of L2 A1.centre
  measures "d8" diameter of A2
  measures "d9" distance of L2 A2.centre
  measures "d10" distance of L0 A2.centre
  measures "d11" diameter of A3
  measures "d12" distance of L1 A3.centre
  measures "d13" distance of L2 A3.centre
extrude "Extrude1" add sketch "Sketch1" along normal blind 1.6
sketch "Sketch2" plane through (0, 0, 1.6) normal (0, 0, 1) x (1, 0, 0)
  circle A0 centre (-18.5, 18.5) radius 1.6
  circle A1 centre (18.5, -18.5) radius 1.6
  circle A2 centre (-18.5, -18.5) radius 1.6
  circle A3 centre (18.5, 18.5) radius 1.6
  line L0 (21.5, 21.5) -> (-21.5, 21.5)
  line L1 (-21.5, 21.5) -> (-21.5, -21.5)
  line L2 (-21.5, -21.5) -> (21.5, -21.5)
  line L3 (21.5, -21.5) -> (21.5, 21.5)
  line L4 (11.5, 2.5) -> (-11.5, 2.5)
  line L5 (-11.5, 2.5) -> (-11.5, 18.5)
  line L6 (-11.5, 18.5) -> (11.5, 18.5)
  line L7 (11.5, 18.5) -> (11.5, 2.5)
  line L8 (11.5, 2.5) -> (-11.5, 18.5) construction
  line L9 (-11.5, 2.5) -> (11.5, 18.5) construction
  point P0 (0, 10.5)
  dimension "d16" = 16
  dimension "d17" = 23
  dimension "d18" = 10
  dimension "d19" = 3
  constraint horizontal L4
  constraint perpendicular L4 L5
  constraint parallel L4 L6
  constraint parallel L5 L7
  constraint coincident L8 P0
  constraint coincident L9 P0
  measures "d16" distance of L4.start L6.end
  measures "d17" distance of L4.start L4.end
  measures "d18" distance of L1 L5
  measures "d19" distance of L0 L6
extrude "Extrude2" add sketch "Sketch2" along normal blind 25 contours L4 L5 L6 L7

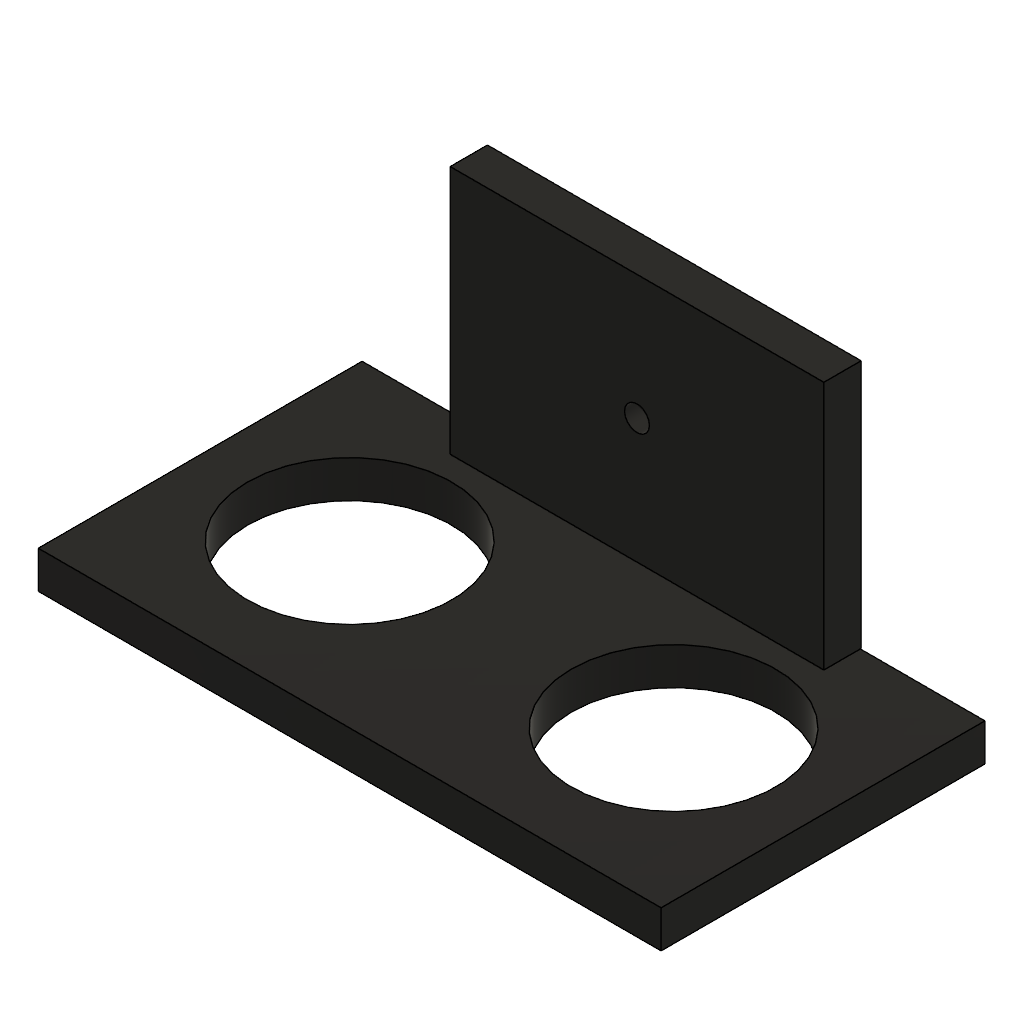
design "Sensor_Bracket"
part number: 2026-11-12-23-32-41-763
Autodesk Fusion 360 part; units mm, degrees
sketch "Sketch1" plane through (0, 0, 0) normal (0, 0, 1) x (1, 0, 0)
  line L0 (15, -10) -> (-15, -10)
  line L1 (-15, -10) -> (-15, 10)
  line L2 (-15, 10) -> (15, 10)
  line L3 (15, 10) -> (15, -10)
  line L4 (15, -10) -> (-15, 10) construction
  line L5 (-15, -10) -> (15, 10) construction
  dimension "d1" = 30
  dimension "d2" = 20
  constraint horizontal L0
  constraint perpendicular L0 L1
  constraint parallel L0 L2
  constraint parallel L1 L3
  constraint coincident L4 origin
  constraint coincident L5 origin
  measures "d1" distance of L0.start L0.end
  measures "d2" distance of L0.start L2.end
extrude "Extrude1" add sketch "Sketch1" along normal blind 3
sketch "Sketch3" plane through (0, -10, 0) normal (0, -1, 0) x (1, 0, 0)
  line L0 (-15, 0) -> (15, 0)
  line L1 (15, 0) -> (15, 3)
  line L2 (15, 3) -> (-15, 3)
  line L3 (-15, 3) -> (-15, 0)
  line L4 (25, 0.0631) -> (-25, 0.0631)
  line L5 (-25, 0.0631) -> (-25, 26.0631)
  line L6 (-25, 26.0631) -> (25, 26.0631)
  line L7 (25, 26.0631) -> (25, 0.0631)
  line L8 (25, 0.0631) -> (-25, 26.0631) construction
  line L9 (-25, 0.0631) -> (25, 26.0631) construction
  dimension "d7" = 50
  dimension "d8" = 26
  constraint horizontal L4
  constraint perpendicular L4 L5
  constraint parallel L4 L6
  constraint parallel L5 L7
  measures "d7" distance of L4.start L4.end
  measures "d8" distance of L4.start L6.end
extrude "Extrude2" add sketch "Sketch3" along normal blind 3 contours L1 L2 L3 L4 L5 L6 L7 | L1 L2 L3 L4
sketch "Sketch4" plane through (0, 0, 3) normal (0, 0, 1) x (1, 0, 0)
  line L0 (15, 10) -> (-15, 10)
  line L1 (-15, 10) -> (-15, -10)
  line L2 (-15, -10) -> (15, -10)
  line L3 (15, -10) -> (15, 10)
  circle A0 centre (0, 0) radius 1
  line L4 (25, -13) -> (-25, -13)
  dimension "d11" = 2
  dimension "d12" = 13
  dimension "d13" = 15
  constraint coincident A0.centre origin
  measures "d11" diameter of A0
  measures "d12" distance of A0.centre L4
  measures "d13" distance of A0.centre L3
extrude "Extrude3" cut sketch "Sketch4" against normal blind 33 contours A0
sketch "Sketch5" plane through (0, -13, 0) normal (0, -1, 0) x (1, 0, 0)
  line L0 (25, 26.0631) -> (-25, 26.0631)
  line L1 (-25, 26.0631) -> (-25, 0.0631)
  line L2 (-25, 0.0631) -> (25, 0.0631)
  line L3 (25, 0.0631) -> (25, 26.0631)
  circle A0 centre (13, 13.0631) radius 8.2
  circle A1 centre (-13, 13.0631) radius 8.2
  dimension "d16" = 16.4
  dimension "d17" = 16.4
  dimension "d18" = 13
  dimension "d19" = 13
  dimension "d20" = 26
  dimension "d21" = 12
  dimension "d22" = 38
  measures "d16" diameter of A0
  measures "d17" diameter of A1
  measures "d18" distance of L0 A1.centre
  measures "d19" distance of L0 A0.centre
  measures "d20" distance of A0.centre A1.centre
  measures "d21" distance of L3 A0.centre
  measures "d22" distance of L3 A1.centre
extrude "Extrude4" cut sketch "Sketch5" against normal blind 35 contours A0 | A1

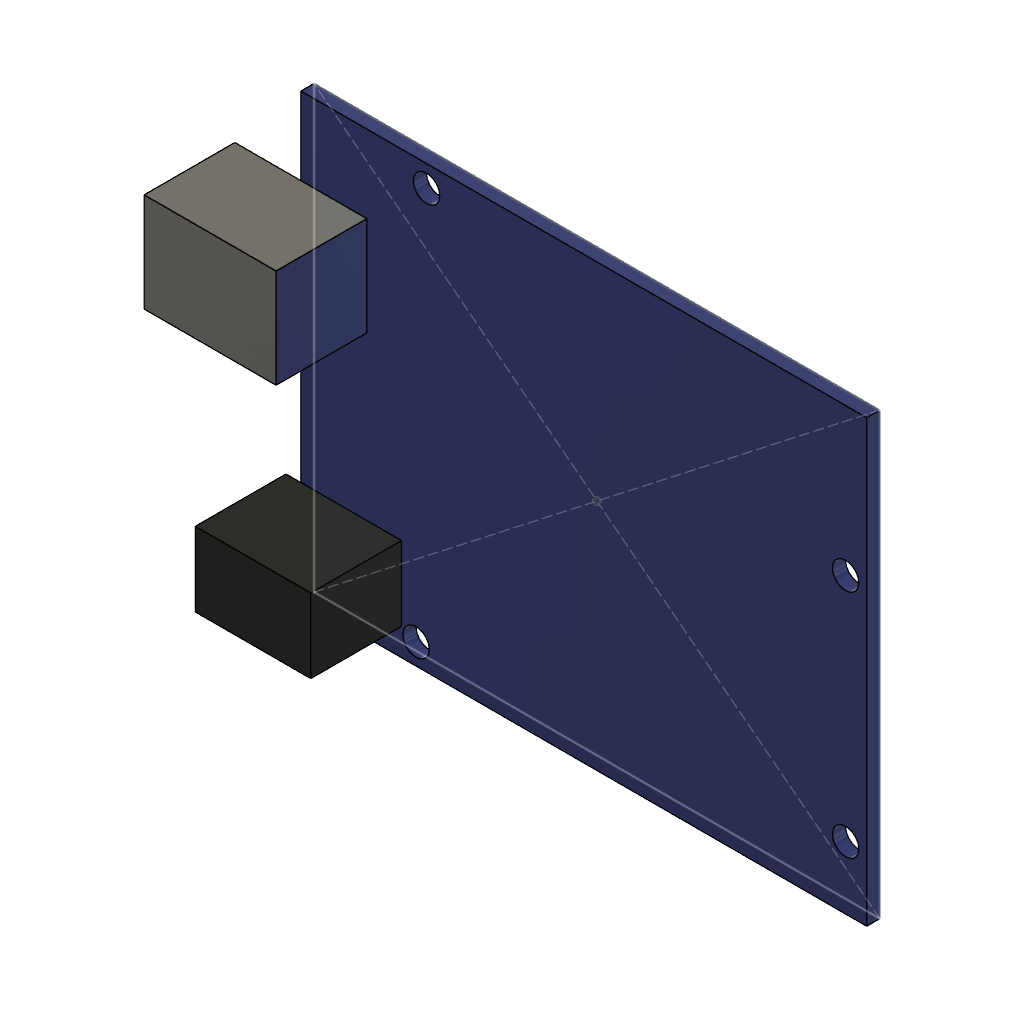
design "Arduino Uno"
part number: 2026-11-09-18-48-16-396
Autodesk Fusion 360 part; units mm, degrees
sketch "Sketch1" plane through (0, 0, 0) normal (0, 0, 1) x (1, 0, 0)
  line L0 (34.3, -26.7) -> (-34.3, -26.7)
  line L1 (-34.3, -26.7) -> (-34.3, 26.7)
  line L2 (-34.3, 26.7) -> (34.3, 26.7)
  line L3 (34.3, 26.7) -> (34.3, -26.7)
  line L4 (34.3, -26.7) -> (-34.3, 26.7) construction
  line L5 (-34.3, -26.7) -> (34.3, 26.7) construction
  dimension "d1" = 68.6
  dimension "d2" = 53.4
  constraint horizontal L0
  constraint perpendicular L0 L1
  constraint parallel L0 L2
  constraint parallel L1 L3
  constraint coincident L4 origin
  constraint coincident L5 origin
  measures "d1" distance of L0.start L0.end
  measures "d2" distance of L0.start L2.end
extrude "Extrude1" add sketch "Sketch1" along normal blind 1.6
sketch "Sketch2" plane through (0, 0, 1.6) normal (0, 0, 1) x (1, 0, 0)
  line L0 (34.3, 26.7) -> (-34.3, 26.7)
  line L1 (-34.3, 26.7) -> (-34.3, -26.7)
  line L2 (-34.3, -26.7) -> (34.3, -26.7)
  line L3 (34.3, -26.7) -> (34.3, 26.7)
  line L4 (-26.3, 5.3) -> (-42.3, 5.3)
  line L5 (-42.3, 5.3) -> (-42.3, 17.3)
  line L6 (-42.3, 17.3) -> (-26.3, 17.3)
  line L7 (-26.3, 17.3) -> (-26.3, 5.3)
  line L8 (-26.3, 5.3) -> (-42.3, 17.3) construction
  line L9 (-42.3, 5.3) -> (-26.3, 17.3) construction
  line L10 (-22.1, -23.4) -> (-36.1, -23.4)
  line L11 (-36.1, -23.4) -> (-36.1, -14.4)
  line L12 (-36.1, -14.4) -> (-22.1, -14.4)
  line L13 (-22.1, -14.4) -> (-22.1, -23.4)
  line L14 (-22.1, -23.4) -> (-36.1, -14.4) construction
  line L15 (-36.1, -23.4) -> (-22.1, -14.4) construction
  point P0 (-34.3, 11.3)
  point P1 (-29.1, -18.9)
  dimension "d5" = 16
  dimension "d6" = 12
  dimension "d7" = 32
  dimension "d11" = 14
  dimension "d12" = 9
  dimension "d13" = 7.8
  dimension "d15" = 5.2
  constraint horizontal L4
  constraint perpendicular L4 L5
  constraint parallel L4 L6
  constraint parallel L5 L7
  constraint coincident L8 P0
  constraint coincident L9 P0
  constraint coincident L1 P0
  constraint horizontal L10
  constraint perpendicular L10 L11
  constraint parallel L10 L12
  constraint parallel L11 L13
  constraint coincident L14 P1
  constraint coincident L15 P1
  measures "d5" distance of L4.start L4.end
  measures "d6" distance of L4.start L6.end
  measures "d7" distance of L2 L4
  measures "d11" distance of L10.start L10.end
  measures "d12" distance of L10.start L12.end
  measures "d13" distance of L2 P1
  measures "d15" distance of L1 P1
extrude "Extrude2" add sketch "Sketch2" along normal blind 11 contours L1 L4 L6 L7 | L1 L4 L5 L6 | L1 L10 L11 L12 | L1 L10 L12 L13
sketch "Sketch3" plane through (0, 0, 1.6) normal (0, 0, 1) x (1, 0, 0)
  line L0 (-22.1, -23.4) -> (-34.3, -23.4)
  line L1 (-34.3, -23.4) -> (-34.3, -26.7)
  line L2 (-34.3, -26.7) -> (34.3, -26.7)
  line L3 (34.3, -26.7) -> (34.3, 26.7)
  line L4 (34.3, 26.7) -> (-34.3, 26.7)
  line L5 (-34.3, 26.7) -> (-34.3, 17.3)
  line L6 (-34.3, 17.3) -> (-26.3, 17.3)
  line L7 (-26.3, 17.3) -> (-26.3, 5.3)
  line L8 (-26.3, 5.3) -> (-34.3, 5.3)
  line L9 (-34.3, 5.3) -> (-34.3, -14.4)
  line L10 (-34.3, -14.4) -> (-22.1, -14.4)
  line L11 (-22.1, -14.4) -> (-22.1, -23.4)
  circle A0 centre (-20.33, -24.16) radius 1.6
  line L12 (-34.3, -26.7) -> (-34.3, 26.7)
  line L13 (34.3, -26.7) -> (-34.3, -26.7)
  circle A1 centre (-19.06, 24.1) radius 1.6
  circle A2 centre (31.74, -19.08) radius 1.6
  circle A3 centre (31.74, 8.86) radius 1.6
  dimension "d18" = 3.2
  dimension "d19" = 13.97
  dimension "d20" = 2.54
  dimension "d21" = 3.2
  dimension "d22" = 15.24
  dimension "d23" = 50.8
  dimension "d24" = 3.2
  dimension "d25" = 66.04
  dimension "d26" = 7.62
  dimension "d27" = 3.2
  dimension "d28" = 66.04
  dimension "d29" = 35.56
  measures "d18" diameter of A0
  measures "d19" distance of A0.centre L12
  measures "d20" distance of A0.centre L13
  measures "d21" diameter of A1
  measures "d22" distance of L12 A1.centre
  measures "d23" distance of L13 A1.centre
  measures "d24" diameter of A2
  measures "d25" distance of L12 A2.centre
  measures "d26" distance of L13 A2.centre
  measures "d27" diameter of A3
  measures "d28" distance of L12 A3.centre
  measures "d29" distance of L13 A3.centre
extrude "Extrude3" cut sketch "Sketch3" against normal blind 10 contours A0 | A1 | A2 | A3
